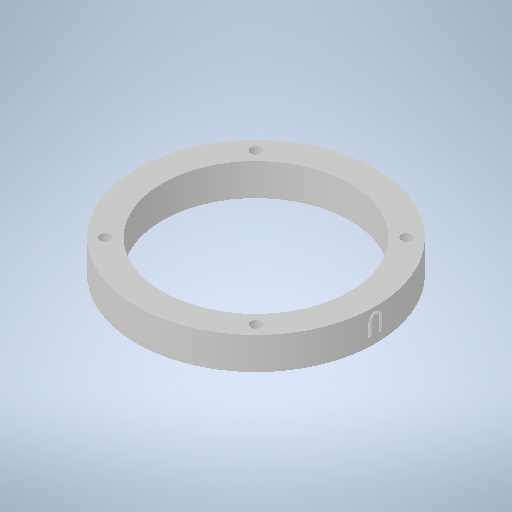
# Autodesk Inventor part: Spool_Base_V2
Saved by Autodesk Inventor 2025.2 (Build 292293000, 293)
## iProperties
Created: 2026-02-14
Part Number: Spool_Base_V2
Material: Generic
Document SubType Name: Modeling
Designer: crazi
Density: 1 g/cm^3
Appearance: Default
Author: crazi
Autodesk Inventor part; units mm, degrees
ref_plane "XZ Plane" through (0, 0, 0) normal (0, 1, 0) x (-1, 0, 0)
ref_plane "XY Plane" through (0, 0, 0) normal (0, 0, 1) x (1, 0, 0)
sketch "Sketch2" plane through (0, 0, 0) normal (0, 1, 0) x (-1, 0, 0)
  circle A0 centre (0, 0) radius 44.65
  circle A1 centre (0, 0) radius 35
  constraints: 2 centre point
extrude "Extrusion1" add sketch "Sketch2" along normal blind 12
sketch "Sketch3" plane through (0, 0, 0) normal (0, 0, 1) x (1, 0, 0)
  line L0 (0, -2.06) -> (0, 12.36) projected
  line L1 (-42.25, 0) -> (-42.25, 5.9)
  line L2 (-42.25, 0) -> (-36.8, 0)
  line L3 (-36.8, 0) -> (-36.8, 10.3)
  line L4 (-36.8, 10.3) -> (-42.25, 10.3)
  line L5 (-42.25, 10.3) -> (-42.25, 10.1)
  arc A0 (-42.25, 10.1) -> (-42.25, 5.9) centre (-40.1076, 8) ccw
  point P0 (0, 0)
  dimension "d132" = 42.25
  dimension "d133" = 5.9
  dimension "d138" = 5.45
  dimension "d139" = 10.3
  dimension "d140" = 270
  dimension "d141" = 5.45
  dimension "d142" = 0.2
  dimension "d143" = 4.2
  dimension "d144" = 3
  constraints: 10 end point, 2 point on circle, 1 centre point, 1 horizontal, 1 perpendicular, 1 vertical
  measures "d132" distance of point (0, 0) L1.start
  measures "d133" distance of L1.start L1.end
  measures "d138" distance of L1.start L2.end
  measures "d139" distance of L2.end L3.end
  measures "d141" distance of L3.end L4.end
  measures "d142" distance of L4.end L5.end
  measures "d143" distance of L5.end L1.end
  measures "d144" radius of A0
revolve "Revolution2" cut sketch "Sketch3" angle 7 mid plane about axis through (0, -10, 0) along (0, 1, 0)
ref_plane "Work Plane4" through (-44.65, 0, 0) normal (1, 0, 0) x (0, 1, 0)
sketch "Sketch17" plane through (-44.65, 0, 0) normal (1, 0, 0) x (0, 1, 0)
  line L0 (3.1, 1.7) -> (3.1, 2.15)
  line L1 (3.1, 2.15) -> (8.1, 2.15)
  line L2 (3.1, 1.7) -> (8.1, 1.7)
  line L3 (3.1, -1.7) -> (3.1, -2.15)
  line L4 (3.1, -2.15) -> (8.1, -2.15)
  line L5 (3.1, -1.7) -> (8.1, -1.7)
  arc A0 (8.1, -1.7) -> (8.1, 1.7) centre (8.1, 0) ccw
  arc A1 (8.1, -2.15) -> (8.1, 2.15) centre (8.1, 0) ccw
  point P0 (0, 0)
  dimension "d146" = 0.45
  dimension "d147" = 5
  dimension "d148" = 5
  dimension "d149" = 3.4
  dimension "d150" = 0.45
  dimension "d151" = 5
  constraints: 12 end point, 4 point on circle, 4 tangent, 2 centre point, 2 perpendicular, 1 horizontal, 1 parallel
  measures "d146" distance of L0.start L0.end
  measures "d147" distance of L0.end L1.end
  measures "d148" distance of L0.start L2.end
  measures "d149" distance of L0.start L3.start
  measures "d150" distance of L3.start L3.end
  measures "d151" distance of L3.end L4.end
extrude "Extrusion11" cut sketch "Sketch17" along normal blind 2.75
chamfer "Chamfer7" distance 0.4 angle 45 8 edges at (-44.6201, 9.4967, -1.6346) (-44.6202, 9.4994, 1.6322) (-44.5982, 5.6, 2.15) (-44.5982, 5.6, -2.15) (-44.6315, 9.2133, -1.2847) (-44.6315, 9.2115, 1.2863) (-44.6176, 5.6, -1.7) (-44.6176, 5.6, 1.7)
chamfer "Chamfer8" distance 1 angle 45 4 edges at (-36.8, 0, 0) (-39.4513, 0, -2.4129) (-39.4513, 0, 2.4129) (-42.25, 0, 0)
mirror "Mirror3" about plane through (0, 0, 0) normal (1, 0, 0) of "Revolution2", "Extrusion11", "Chamfer7", "Chamfer8"
sketch "Sketch18" plane through (0, 12, 0) normal (0, 1, 0) x (1, 0, 0)
  circle A0 centre (0, 0) radius 44.65 projected
  line L0 (0, 0) -> (44.65, 0) construction
  circle A1 centre (0, 0) radius 35 projected
  circle A2 centre (28.1605, 28.1605) radius 2
  dimension "d162" = 4
  constraints: 2 end point, 1 centre point, 1 horizontal
  measures "d162" diameter of A2
extrude "Extrusion12" cut sketch "Sketch18" against normal blind 7 contours A2
chamfer "Chamfer9" distance 2 angle 45 1 edges at (26.1605, 5, -28.1605)
pattern_circular "Circular Pattern2" count 4 over 360 about axis through (0, 0, 0) along (0, 1, 0) of "Extrusion12", "Chamfer9"
body "Solid2"
